Autodesk Fusion 360 part; units mm, degrees
(part 3 of 3)
equation "at_active = 15 mm" comment "Screen area mark: groove centre line (0.85 in 128 x 128 active area ~15.2)"
equation "at_tick = 2 mm" comment "Scale tick pitch on the frame"
equation "at_count = 6" comment "Number of mock-ups"
named bodies: "drop_plate"
